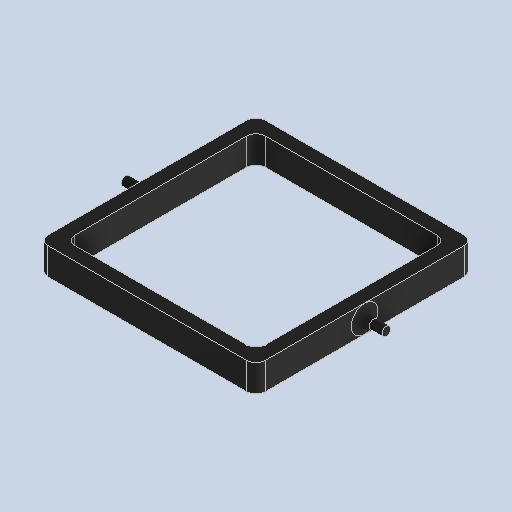
# Autodesk Inventor part: Stabilisatuer1.1
Saved by Autodesk Inventor 2025.3 (Build 293356000, 356)
## iProperties
Created: 2025-04-25
Part Number: Stabilisatuer1.1
Material: Gummi
Document SubType Name: Modeling
Designer: karle
Density: 0.93 g/cm^3
Appearance: Gummi - Schwarz
Author: karle
Autodesk Inventor part; units mm, degrees
ref_plane "YZ Plane" through (0, 0, 0) normal (1, 0, 0) x (0, 1, 0)
ref_plane "XZ Plane" through (0, 0, 0) normal (0, 1, 0) x (-1, 0, 0)
ref_plane "XY Plane" through (0, 0, 0) normal (0, 0, 1) x (1, 0, 0)
sketch "Skizze1" plane through (0, 0, 0) normal (0, 0, 1) x (1, 0, 0)
  line L0 (-60.1832, 60) -> (59.8168, 60)
  line L1 (59.8168, 60) -> (59.8168, -60)
  line L2 (59.8168, -60) -> (-60.1832, -60)
  line L3 (-60.1832, -60) -> (-60.1832, 60)
  line L4 (-52.6832, 52.5) -> (52.3168, 52.5)
  line L5 (52.3168, 52.5) -> (52.3168, -52.5)
  line L6 (52.3168, -52.5) -> (-52.6832, -52.5)
  line L7 (-52.6832, -52.5) -> (-52.6832, 52.5)
  line L8 (-85.838, 0) -> (120.1384, 0)
  line L9 (-0.1832, 77.2993) -> (-0.1832, -74.2156)
  point P0 (0, 0)
  dimension "d0" = 105
  dimension "d1" = 120
  dimension "d2" = 120
  constraints: 20 end point, 4 parallel, 3 horizontal, 3 perpendicular, 1 vertical, 1 other
  measures "d0" distance of L4.start L4.end
  measures "d1" distance of L0.start L0.end
  measures "d2" distance of L0.end L1.end
extrude "Extrusion1" add sketch "Skizze1" along normal blind 15 contours L0 L9 L4 L7 L8 L3 | L0 L1 L8 L5 L4 L9 | L8 L7 L6 L9 L2 L3 | L1 L2 L9 L6 L5 L8
fillet "Rundung1" radius 5 8 edges at (-60.1832, 60, 7.5) (59.8168, 60, 7.5) (-60.1832, -60, 7.5) (59.8168, -60, 7.5) (52.3168, 52.5, 7.5) (-52.6832, 52.5, 7.5) (-52.6832, -52.5, 7.5) (52.3168, -52.5, 7.5)
sketch "Skizze2" plane through (59.8168, -55, 0) normal (1, 0, 0) x (0, 0, -1)
  circle A0 centre (-7.5, 55) radius 2.4
  line L0 (-7.5, -57.2276) -> (-7.5, 156.6251)
  line L1 (0, 0) -> (0, 110) projected
  line L2 (-15, -5) -> (0, -5) projected
  point P0 (0, 55)
  dimension "d6" = 4.8
  dimension "d7" = 7.5
  dimension "d11" = 60
  constraints: 2 end point, 1 centre point, 1 coincident, 1 point on line, 1 vertical
  measures "d6" diameter of A0
  measures "d7" distance between parallel lines of L0 L1
  measures "d11" distance from line of L2 point (-7.5, 55)
extrude "Extrusion2" add sketch "Skizze2" along normal blind 12
sketch "Skizze3" plane through (-60.1832, -55, 0) normal (-1, 0, 0) x (0, 0, 1)
  circle A0 centre (7.5, 55) radius 2.4 projected
  circle A1 centre (7.5, 55) radius 2.4
  point P0 (0, 55)
  dimension "d14" = 4.8
  constraints: 1 centre point, 1 coincident
  measures "d14" diameter of A1
extrude "Extrusion3" add sketch "Skizze3" along normal blind 12
fillet "Rundung2" radius 5 2 edges at (-60.1832, 0, 5.1) (59.8168, 0, 9.9)
